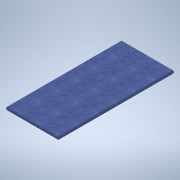
# Autodesk Inventor part: front_usa_box_tevi_apa
Saved by Autodesk Inventor 2022.6 (Build 266554000, 554)
## iProperties
Created: 2026-11-01
Part Number: front_usa_box_tevi_apa
Material: Generic
Document SubType Name: Modeling
Designer: Dragos Macovei
Density: 1 g/cm^3
Appearance: Default
Author: Dragos Macovei
Autodesk Inventor part; units mm, degrees
ref_plane "YZ Plane" through (0, 0, 0) normal (1, 0, 0) x (0, 1, 0)
ref_plane "XZ Plane" through (0, 0, 0) normal (0, 1, 0) x (-1, 0, 0)
ref_plane "XY Plane" through (0, 0, 0) normal (0, 0, 1) x (1, 0, 0)
sketch "Sketch1" plane through (0, 0, 0) normal (0, 1, 0) x (-1, 0, 0)
  line L0 (0, 0) -> (346, 0)
  line L1 (346, 0) -> (346, 765)
  line L2 (346, 765) -> (0, 765)
  line L3 (0, 765) -> (0, 0)
  point P0 (346, 382.5)
  dimension "d0" = 765
  dimension "d1" = 346
  constraints: 8 end point, 2 parallel, 1 horizontal, 1 midpoint, 1 perpendicular
  measures "d0" distance of L0.end L1.end
  measures "d1" distance from line of L3 point (346, 382.5)
extrude "Extrusion1" add sketch "Sketch1" along normal blind 18
fillet "Fillet1" radius 5 4 edges at (-346, 18, 382.5) (-173, 18, 765) (0, 18, 382.5) (-173, 18, 0)
body "Solid1"
